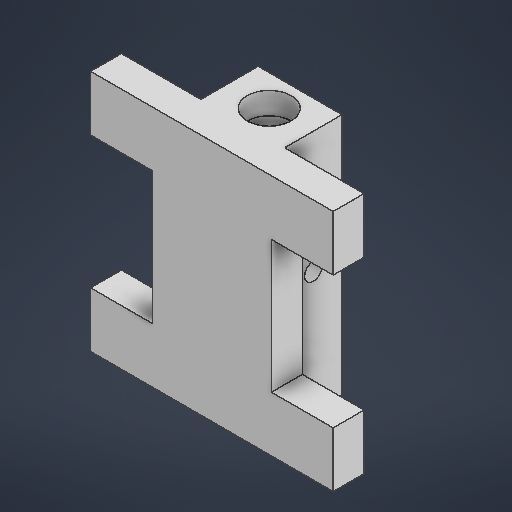
# Autodesk Inventor part: trasePinza
Saved by Autodesk Inventor 2027.1 (Build 311270010, 270A)
## iProperties
Created: 2026-11-02
Part Number: trasePinza
Material: Genérico
Document SubType Name: Modeling
Designer: MANGEL
Density: 1 g/cm^3
Appearance: Valor por defecto
Author: MANGEL
Autodesk Inventor part; units mm, degrees
ref_plane "YZ Plane" through (0, 0, 0) normal (1, 0, 0) x (0, 1, 0)
ref_plane "XZ Plane" through (0, 0, 0) normal (0, 1, 0) x (-1, 0, 0)
ref_plane "XY Plane" through (0, 0, 0) normal (0, 0, 1) x (1, 0, 0)
sketch "Boceto1" plane through (0, 0, 0) normal (0, 1, 0) x (-1, 0, 0)
  line L0 (27.5, 10) -> (-27.5, 10)
  line L1 (-27.5, 10) -> (-27.5, -10)
  line L2 (-27.5, -10) -> (27.5, -10)
  line L3 (27.5, -10) -> (27.5, 10)
  line L4 (27.5, 10) -> (-27.5, -10) construction
  line L5 (-27.5, 10) -> (27.5, -10) construction
  line L6 (0, -10) -> (0, 10) construction
  line L7 (9.5, -10) -> (27.5, -10)
  line L8 (27.5, -10) -> (27.5, 3)
  line L9 (27.5, 3) -> (9.5, 3)
  line L10 (9.5, 3) -> (9.5, -10)
  line L11 (-27.5, 3) -> (-9.5, 3)
  line L12 (-9.5, 3) -> (-9.5, -10)
  point P0 (0, 0)
  point P1 (-9.5, -10)
  dimension "d0" = 55
  dimension "d1" = 20
  dimension "d2" = 18
  dimension "d4" = 7
  constraints: 26 end point, 4 midpoint, 4 parallel, 3 symmetric about line, 2 horizontal, 2 perpendicular, 2 point on line
  measures "d0" distance of L1.end L2.end
  measures "d1" distance of L0.end L1.end
  measures "d2" distance of L8.end L9.end
  measures "d4" distance between parallel lines of L0 L9
extrude "Extrusión1" add sketch "Boceto1" along normal blind 55 contours L3 L9 L10 L2 L12 L11 L1 L0
sketch "Boceto2" plane through (0, 55, 0) normal (0, 1, 0) x (1, 0, 0)
  circle A0 centre (0, 3) radius 5
  line L0 (-27.5, -10) -> (27.5, -10) projected
  point P0 (0, 0)
  point P1 (0, -10)
  point P2 (0, -10)
  dimension "d9" = 10
  dimension "d10" = 13
  constraints: 2 midpoint, 1 centre point, 1 vertical alignment
  measures "d9" diameter of A0
  measures "d10" distance of point (0, -10) A0.centre
extrude "Extrusión2" cut sketch "Boceto2" against normal blind 5
sketch "Boceto3" plane through (9.5, 0, 3) normal (1, 0, 0) x (0, 0, -1)
  circle A0 centre (6.5, 27.5) radius 2
  line L0 (13, 0) -> (13, 55) projected
  line L1 (0, 55) -> (13, 55) projected
  point P0 (3, 0)
  point P1 (13, 27.5)
  point P2 (6.5, 55)
  dimension "d13" = 4
  constraints: 2 midpoint, 1 centre point, 1 horizontal alignment, 1 vertical alignment
  measures "d13" diameter of A0
extrude "Extrusión3" cut sketch "Boceto3" against normal through all
sketch "Boceto4" plane through (27.5, 0, 3) normal (0, 0, -1) x (-1, 0, 0)
  line L0 (0, 0) -> (0, 55) projected
  line L1 (0, 42.5) -> (14, 42.5)
  line L2 (14, 42.5) -> (14, 12.5)
  line L3 (14, 12.5) -> (0, 12.5)
  line L4 (0, 12.5) -> (0, 42.5)
  line L5 (22.5, 55) -> (32.5, 55) construction
  line L6 (27.5, 55) -> (27.5, 0) construction
  line L7 (55, 0) -> (55, 55) projected
  line L8 (55, 42.5) -> (41, 42.5)
  line L9 (41, 42.5) -> (41, 12.5)
  line L10 (41, 12.5) -> (55, 12.5)
  point P0 (14, 27.5)
  point P1 (55, 27.5)
  dimension "d16" = 14
  dimension "d17" = 30
  constraints: 16 end point, 4 symmetric about line, 3 midpoint, 2 parallel, 1 horizontal, 1 horizontal alignment, 1 perpendicular, 1 point on line, 1 vertical
  measures "d16" distance of L1.start L1.end
  measures "d17" distance of L1.end L2.end
extrude "Extrusión4" cut sketch "Boceto4" against normal through all
